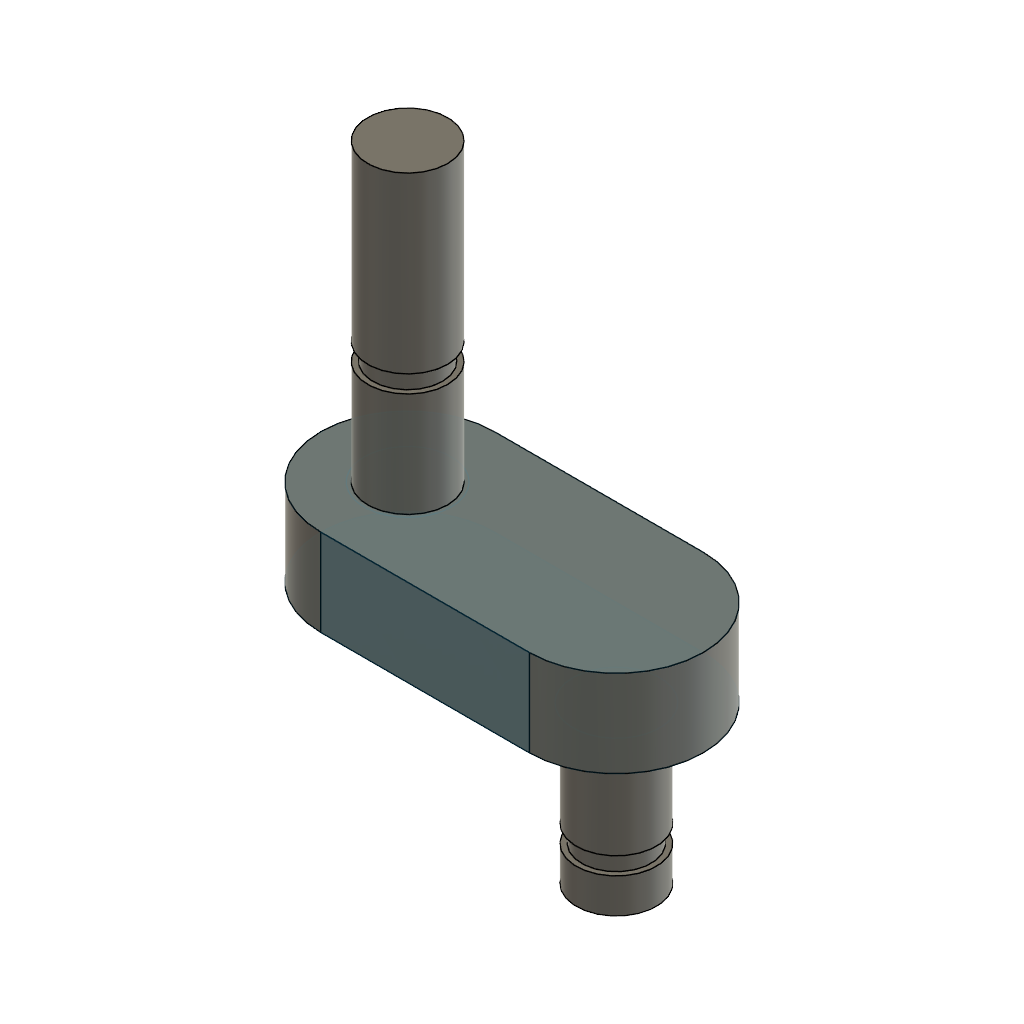
link 2 (Autodesk Fusion 360 design; units mm, degrees)
part number: 2026-11-18-20-16-21-113
Autodesk Fusion 360 part; units mm, degrees
sketch "Sketch1" plane through (0, 0, 0) normal (0, 1, 0) x (1, 0, 0)
  line L0 (0, -5) -> (12, -5)
  line L1 (0, 5) -> (12, 5)
  arc A0 (0, 5) -> (0, -5) centre (0, 0) ccw
  arc A1 (12, -5) -> (12, 5) centre (12, 0) ccw
  circle A2 centre (0, 0) radius 2.5
  circle A3 centre (12, 0) radius 2.5
  dimension "d1" = 10
  dimension "d2" = 12
  dimension "d3" = 5
  dimension "d4" = 10
  dimension "d5" = 5
  dimension "d6" = 5
  constraint coincident A0.centre A2.centre
  constraint horizontal L0
  constraint horizontal L1
  constraint concentric A0 A2
  constraint concentric A1 A3
  measures "d1" diameter of A0
  measures "d2" distance of L0.start L0.end
  measures "d3" distance of L0.end A1.centre
  measures "d4" distance of L0 L1
  measures "d5" diameter of A2
  measures "d6" diameter of A3
extrude "Extrude2" add sketch "Sketch1" along normal blind 5 makes body 1
sketch "Sketch2" plane through (0, 0, 0) normal (0, -1, 0) x (1, 0, 0)
  circle A0 centre (12, 0) radius 2.5
  circle A1 centre (0, 0) radius 2.5
  arc A2 (0, 5) -> (0, -5) centre (0, 0) ccw
  line L0 (0, -5) -> (12, -5)
  arc A3 (12, -5) -> (12, 5) centre (12, 0) ccw
  line L1 (12, 5) -> (0, 5)
  circle A4 centre (0, 0) radius 2.5
  circle A5 centre (12, 0) radius 2.5
  dimension "d11" = 5
  dimension "d12" = 5
  constraint coincident A1.centre A2.centre
  constraint concentric A0 A5
  measures "d11" diameter of A4
  measures "d12" diameter of A5
extrude "Extrude3" add sketch "Sketch2" against normal blind 10 contours A1 A4 bodies 1
sketch "Sketch3" plane through (0, 10, 0) normal (0, 1, 0) x (-1, 0, 0)
  circle A0 centre (0, 0) radius 2.5
  circle A1 centre (0, 0) radius 2.45
  dimension "d15" = 4.9
  constraint coincident A0.centre A1.centre
  measures "d15" diameter of A1
extrude "Extrude4" add sketch "Sketch3" along normal blind 1 contours A1 bodies 1
sketch "Sketch4" plane through (0, 11, 0) normal (0, 1, 0) x (-1, 0, 0)
  circle A0 centre (0, 0) radius 2.45
  circle A1 centre (0, 0) radius 2.5
  dimension "d18" = 5
  constraint coincident A0.centre A1.centre
  measures "d18" diameter of A1
extrude "Extrude5" add sketch "Sketch4" along normal blind 1 separate body makes body 2
extrude "Extrude6" add 1 faces at (0.5455, 11, -0.5061) along direction (0, 1, 0) blind 1 on bodies 1 bodies 1 2
sketch "Sketch5" plane through (0, 0, 0) normal (0, -1, 0) x (1, 0, 0)
  circle A0 centre (12, 0) radius 2.5
  arc A1 (0, 5) -> (0, -5) centre (0, 0) ccw
  line L0 (0, -5) -> (12, -5)
  arc A2 (12, -5) -> (12, 5) centre (12, 0) ccw
  line L1 (12, 5) -> (0, 5)
sketch "Sketch6" plane through (0, 5, 0) normal (0, 1, 0) x (-1, 0, 0)
  circle A0 centre (-12, 0) radius 2.5
  circle A1 centre (0, 0) radius 2.5
  arc A2 (0, -5) -> (0, 5) centre (0, 0) ccw
  line L0 (0, 5) -> (-12, 5)
  arc A3 (-12, 5) -> (-12, -5) centre (-12, 0) ccw
  line L1 (-12, -5) -> (0, -5)
  circle A4 centre (-12, 0) radius 2.5
  dimension "d23" = 5
  constraint concentric A0 A4
  measures "d23" diameter of A4
extrude "Extrude7" add sketch "Sketch6" against normal blind 10 contours A0 A4 bodies 1
sketch "Sketch7" plane through (0, -5, 0) normal (0, -1, 0) x (1, 0, 0)
  circle A0 centre (12, 0) radius 2.5
  circle A1 centre (12, 0) radius 2.45
  dimension "d26" = 4.9
  constraint concentric A0 A1
  measures "d26" diameter of A1
extrude "Extrude8" add sketch "Sketch7" along normal blind 1 contours A1 bodies 1
sketch "Sketch8" plane through (0, -6, 0) normal (0, -1, 0) x (1, 0, 0)
  circle A0 centre (12, 0) radius 2.45
  circle A1 centre (12, 0) radius 2.5
  dimension "d29" = 5
  constraint concentric A0 A1
  measures "d29" diameter of A1
extrude "Extrude9" add sketch "Sketch8" along normal blind 1 separate body makes body 3
extrude "Extrude10" add 1 faces at (12.5895, -6, 0.6772) along direction (0, -1, 0) blind 1 on bodies 1 bodies 1 3
extrude "Extrude11" add 1 faces at (12.643, -7, -0.1378) along direction (0, -1, 0) blind 8 on bodies 1 bodies 1
sketch "Sketch9" plane through (0, 12, 0) normal (0, 1, 0) x (-1, 0, 0)
  circle A0 centre (0, 0) radius 2.5
sketch "Sketch10" plane through (0, 0, 0) normal (0, -1, 0) x (1, 0, 0)
  circle A0 centre (0, 0) radius 2.3
  dimension "d36" = 4.6
  constraint coincident A0.centre origin
  measures "d36" diameter of A0
extrude "Extrude12" cut sketch "Sketch9" against normal blind 13 bodies 1
extrude "Extrude13" add sketch "Sketch10" against normal blind 10 separate body makes body 4
extrude "Extrude14" add 1 faces at (0.6867, 10, 1.0676) along direction (0, 1, 0) blind 2 on bodies 4 bodies 4
sketch "Sketch11" plane through (0, 12, 0) normal (0, 1, 0) x (-1, 0, 0)
  circle A0 centre (0, 0) radius 2.3
sketch "Sketch12" plane through (0, 5, 0) normal (0, 1, 0) x (-1, 0, 0)
  circle A0 centre (0, 0) radius 2.5
  arc A1 (0, -5) -> (0, 5) centre (0, 0) ccw
  line L0 (0, 5) -> (-12, 5)
  arc A2 (-12, 5) -> (-12, -5) centre (-12, 0) ccw
  line L1 (-12, -5) -> (0, -5)
extrude "Extrude15" cut 1 faces at (12.643, -15, -0.1378) along direction (0, 1, 0) blind 32 on bodies 1 bodies 1
sketch "Sketch13" plane through (0, 5, 0) normal (0, 1, 0) x (-1, 0, 0)
  circle A0 centre (-12, 0) radius 2.5
  dimension "d45" = 5
  measures "d45" diameter of A0
extrude "Extrude16" add sketch "Sketch13" against normal blind 6 bodies 1
sketch "Sketch14" plane through (0, 5, 0) normal (0, 1, 0) x (-1, 0, 0)
sketch "Sketch15" plane through (0, -1, 0) normal (0, -1, 0) x (1, 0, 0)
  circle A0 centre (12, 0) radius 2.5
  circle A1 centre (12, 0) radius 2.45
  dimension "d48" = 4.9
  constraint concentric A0 A1
  measures "d48" diameter of A1
extrude "Extrude17" cut sketch "Sketch15" against normal blind 1 bodies 1
extrude "Extrude18" add 1 faces at (11.237, -1, -0.4733) along direction (0, -1, 0) blind 8 on bodies 1 bodies 1
extrude "Extrude19" add 1 faces at (11.237, -9, -0.4733) along direction (0, -1, 0) blind 5 on bodies 1 bodies 1
sketch "Sketch16" plane through (0, -14, 0) normal (0, -1, 0) x (1, 0, 0)
  circle A0 centre (12, 0) radius 2.45
  circle A1 centre (12, 0) radius 2.3
  dimension "d55" = 4.6
  constraint concentric A0 A1
  measures "d55" diameter of A1
extrude "Extrude20" cut sketch "Sketch16" against normal blind 14 bodies 1
sketch "Sketch17" plane through (0, 12, 0) normal (0, 1, 0) x (-1, 0, 0)
  circle A0 centre (0, 0) radius 2.3
  dimension "d58" = 4.6
  constraint coincident A0.centre origin
  measures "d58" diameter of A0
extrude "Extrude21" cut sketch "Sketch11" against normal blind 17 bodies 4
sketch "Sketch18" plane through (0, 0, 0) normal (0, -1, 0) x (1, 0, 0)
  circle A0 centre (0, 0) radius 2.5
  dimension "d61" = 5
  constraint coincident A0.centre origin
  measures "d61" diameter of A0
extrude "Extrude22" add sketch "Sketch18" against normal blind 5 bodies 1 4
extrude "Extrude23" add sketch "Sketch17" against normal blind 7 bodies 1
sketch "Sketch19" plane through (0, 12, 0) normal (0, 1, 0) x (-1, 0, 0)
  circle A0 centre (0, 0) radius 2.3
extrude "Extrude24" add sketch "Sketch19" along normal blind 2 bodies 1
extrude "Extrude25" cut 1 faces at (-0.6867, 14, 1.0676) along direction (0, -1, 0) blind 4 on bodies 1 bodies 1
sketch "Sketch20" plane through (0, 10, 0) normal (0, 1, 0) x (-1, 0, 0)
  circle A0 centre (0, 0) radius 2.3
  circle A1 centre (0, 0) radius 2
  dimension "d70" = 4
  constraint coincident A0.centre A1.centre
  measures "d70" diameter of A1
extrude "Extrude26" add sketch "Sketch20" along normal blind 1 contours A1 bodies 1
sketch "Sketch21" plane through (0, 11, 0) normal (0, 1, 0) x (-1, 0, 0)
  circle A0 centre (0, 0) radius 2
  circle A1 centre (0, 0) radius 2.3
  dimension "d73" = 4.6
  constraint concentric A0 A1
  measures "d73" diameter of A1
extrude "Extrude27" add sketch "Sketch21" along normal blind 1 contours A0 | A1 bodies 1
sketch "Sketch22" plane through (0, 0, 0) normal (0, -1, 0) x (1, 0, 0)
sketch "Sketch23" plane through (0, 0, 5) normal (0, 0, 1) x (-1, 0, 0)
  line L0 (0, 0) -> (-12, 0)
  line L1 (-12, 0) -> (-12, -5)
  line L2 (-12, -5) -> (0, -5)
  line L3 (0, -5) -> (0, 0)
extrude "Extrude28" cut 1 faces at (-0.6867, 12, 1.0676) along direction (0, -1, 0) blind 2 on bodies 1 bodies 1
extrude "Extrude29" add 1 faces at (-0.6867, 10, 1.0676) along direction (0, 1, 0) blind 1 on bodies 1 bodies 1
sketch "Sketch24" plane through (0, 11, 0) normal (0, 1, 0) x (-1, 0, 0)
  circle A0 centre (0, 0) radius 2.3
  circle A1 centre (0, 0) radius 2
  dimension "d80" = 4
  constraint coincident A0.centre A1.centre
  measures "d80" diameter of A1
extrude "Extrude30" add sketch "Sketch24" along normal blind 1 contours A1 bodies 1
sketch "Sketch25" plane through (0, 12, 0) normal (0, 1, 0) x (-1, 0, 0)
  circle A0 centre (0, 0) radius 2
  circle A1 centre (0, 0) radius 2.3
  dimension "d83" = 4.6
  constraint coincident A0.centre A1.centre
  measures "d83" diameter of A1
extrude "Extrude31" add sketch "Sketch25" along normal blind 2 contours A0 | A1 bodies 1
extrude "Extrude32" cut 1 faces at (13.2679, -14, -0.0609) along direction (0, 1, 0) blind 9 on bodies 1 bodies 1
sketch "Sketch26" plane through (0, -5, 0) normal (0, -1, 0) x (1, 0, 0)
  circle A0 centre (12, 0) radius 2.3
  circle A1 centre (12, 0) radius 2
  dimension "d88" = 4
  constraint concentric A0 A1
  measures "d88" diameter of A1
extrude "Extrude33" add sketch "Sketch26" along normal blind 1 contours A1 bodies 1
sketch "Sketch27" plane through (0, -6, 0) normal (0, -1, 0) x (1, 0, 0)
  circle A0 centre (12, 0) radius 2
  circle A1 centre (12, 0) radius 2.3
  dimension "d91" = 4.6
  constraint concentric A0 A1
  measures "d91" diameter of A1
extrude "Extrude34" add sketch "Sketch27" along normal blind 8 contours A0 | A1 bodies 1
sketch "Sketch28" plane through (0, 0, 0) normal (0, -1, 0) x (1, 0, 0)
sketch "Sketch29" plane through (0, 0, 5) normal (0, 0, 1) x (-1, 0, 0)
extrude "Extrude35" cut 1 faces at (12.0522, -14, 0.6966) along direction (0, 1, 0) blind 9 on bodies 1 bodies 1
extrude "Extrude36" add 1 faces at (13.2679, -5, -0.0609) along direction (0, -1, 0) blind 1 on bodies 1 bodies 1
sketch "Sketch30" plane through (0, 0, 0) normal (0, -1, 0) x (1, 0, 0)
sketch "Sketch31" plane through (0, -6, 0) normal (0, -1, 0) x (1, 0, 0)
  circle A0 centre (12, 0) radius 2.3
  circle A1 centre (12, 0) radius 2
  dimension "d98" = 4
  constraint concentric A0 A1
  measures "d98" diameter of A1
extrude "Extrude37" add sketch "Sketch31" along normal blind 1 contours A1 bodies 1
sketch "Sketch32" plane through (0, -7, 0) normal (0, -1, 0) x (1, 0, 0)
  circle A0 centre (12, 0) radius 2
  circle A1 centre (12, 0) radius 2.3
  dimension "d101" = 4.6
  constraint concentric A0 A1
  measures "d101" diameter of A1
extrude "Extrude38" add sketch "Sketch32" along normal blind 7 contours A0 | A1 bodies 1
extrude "Extrude39" cut 1 faces at (12.0522, -14, 0.6966) along direction (0, 1, 0) blind 5 on bodies 1 bodies 1
extrude "Extrude40" add 1 faces at (-0.6867, 14, 1.0676) along direction (0, 1, 0) blind 8 on bodies 1 bodies 1
